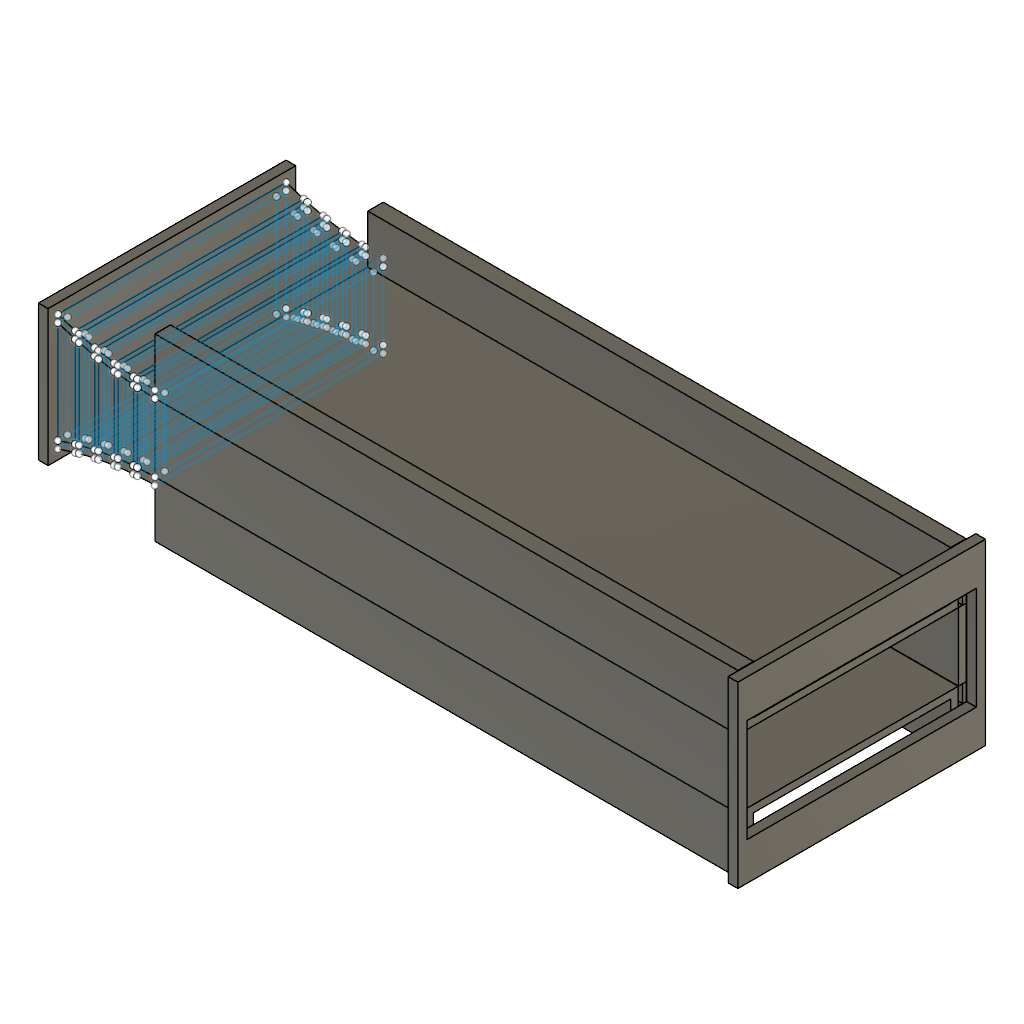
Magnetide-A-printable (Autodesk Fusion 360 design; units mm, degrees)
part number: 2026-10-21-00-04-49-115
Autodesk Fusion 360 part; units mm, degrees
ref_plane "WorkPlane1" through (60, 0, 0) normal (1, 0, 0) x (0, 1, 0)
sketch "plate_a" plane through (60, 0, 0) normal (1, 0, 0) x (0, 0, -1)
  line L0 (-7, -21.85) -> (-7, 21.85)
  line L1 (-7, 21.85) -> (-10.5, 21.85)
  line L2 (-10.5, 21.85) -> (-10.5, 22.75)
  line L3 (-10.5, 22.75) -> (-7, 22.75)
  line L4 (-7, 22.75) -> (-7, 23.5)
  line L5 (-7, 23.5) -> (-18.5, 23.5)
  line L6 (-18.5, 23.5) -> (-18.5, 20.3)
  line L7 (-18.5, 20.3) -> (-8.5, 20.3)
  line L8 (-8.5, 20.3) -> (-8.5, -20.3)
  line L9 (-8.5, -20.3) -> (-18.5, -20.3)
  line L10 (-18.5, -20.3) -> (-18.5, -23.5)
  line L11 (-18.5, -23.5) -> (-7, -23.5)
  line L12 (-7, -23.5) -> (-7, -22.75)
  line L13 (-7, -22.75) -> (-10.5, -22.75)
  line L14 (-10.5, -22.75) -> (-10.5, -21.85)
  line L15 (-10.5, -21.85) -> (-7, -21.85)
extrude "Extrude1" add sketch "plate_a" along normal mid plane 120 makes body 1
ref_plane "WorkPlane2" through (60, 0, 0) normal (1, 0, 0) x (0, 1, 0)
sketch "plate_b" plane through (60, 0, 0) normal (1, 0, 0) x (0, 0, -1)
  line L0 (7, -21.85) -> (7, 21.85)
  line L1 (7, 21.85) -> (10.5, 21.85)
  line L2 (10.5, 21.85) -> (10.5, 22.75)
  line L3 (10.5, 22.75) -> (7, 22.75)
  line L4 (7, 22.75) -> (7, 23.5)
  line L5 (7, 23.5) -> (18.5, 23.5)
  line L6 (18.5, 23.5) -> (18.5, 20.3)
  line L7 (18.5, 20.3) -> (8.5, 20.3)
  line L8 (8.5, 20.3) -> (8.5, -20.3)
  line L9 (8.5, -20.3) -> (18.5, -20.3)
  line L10 (18.5, -20.3) -> (18.5, -23.5)
  line L11 (18.5, -23.5) -> (7, -23.5)
  line L12 (7, -23.5) -> (7, -22.75)
  line L13 (7, -22.75) -> (10.5, -22.75)
  line L14 (10.5, -22.75) -> (10.5, -21.85)
  line L15 (10.5, -21.85) -> (7, -21.85)
extrude "Extrude2" add sketch "plate_b" along normal mid plane 120 separate body makes body 2
ref_plane "WorkPlane3" through (0, -22.7, 0) normal (0, 1, 0) x (0, 0, 1)
sketch "rail_left" plane through (0, -22.7, 0) normal (0, 1, 0) x (1, 0, 0)
  line L0 (0, 7) -> (120, 7)
  line L1 (120, 7) -> (120, -7)
  line L2 (120, -7) -> (0, -7)
  line L3 (0, -7) -> (0, 7)
extrude "Extrude3" add sketch "rail_left" along normal mid plane 1.6 separate body makes body 3
ref_plane "WorkPlane4" through (0, 22.7, 0) normal (0, 1, 0) x (0, 0, 1)
sketch "rail_right" plane through (0, 22.7, 0) normal (0, 1, 0) x (1, 0, 0)
  line L0 (0, 7) -> (120, 7)
  line L1 (120, 7) -> (120, -7)
  line L2 (120, -7) -> (0, -7)
  line L3 (0, -7) -> (0, 7)
extrude "Extrude4" add sketch "rail_right" along normal mid plane 1.6 separate body makes body 4
ref_plane "WorkPlane5" through (-20, 0, 0) normal (1, 0, 0) x (0, 1, 0)
sketch "Sketch5" plane through (-20, 0, 0) normal (1, 0, 0) x (0, 0, -1)
  line L0 (-12, -23.5) -> (-10.5, -23.5)
  line L1 (-10.5, -23.5) -> (-10.5, 23.5)
  line L2 (-10.5, 23.5) -> (-12, 23.5)
  line L3 (-12, 23.5) -> (-12, -23.5)
ref_plane "WorkPlane6" through (-15.6, 0, 0) normal (1, 0, 0) x (0, 1, 0)
sketch "Sketch6" plane through (-15.6, 0, 0) normal (1, 0, 0) x (0, 0, -1)
  line L0 (-10.6294, -23.5) -> (-9.1294, -23.5)
  line L1 (-9.1294, -23.5) -> (-9.1294, 23.5)
  line L2 (-9.1294, 23.5) -> (-10.6294, 23.5)
  line L3 (-10.6294, 23.5) -> (-10.6294, -23.5)
loft "Loft1" add profiles "Sketch5", "Sketch6" section 1 section 2 separate body makes body 5
ref_plane "WorkPlane7" through (-16.4, 0, 0) normal (1, 0, 0) x (0, 1, 0)
sketch "Sketch7" plane through (-16.4, 0, 0) normal (1, 0, 0) x (0, 0, -1)
  line L0 (-10.8534, -23.5) -> (-9.3534, -23.5)
  line L1 (-9.3534, -23.5) -> (-9.3534, 23.5)
  line L2 (-9.3534, 23.5) -> (-10.8534, 23.5)
  line L3 (-10.8534, 23.5) -> (-10.8534, -23.5)
ref_plane "WorkPlane8" through (-11.6, 0, 0) normal (1, 0, 0) x (0, 1, 0)
sketch "Sketch8" plane through (-11.6, 0, 0) normal (1, 0, 0) x (0, 0, -1)
  line L0 (-9.6774, -23.5) -> (-8.1774, -23.5)
  line L1 (-8.1774, -23.5) -> (-8.1774, 23.5)
  line L2 (-8.1774, 23.5) -> (-9.6774, 23.5)
  line L3 (-9.6774, 23.5) -> (-9.6774, -23.5)
loft "Loft2" add profiles "Sketch7", "Sketch8" section 1 section 2 separate body makes body 6
ref_plane "WorkPlane9" through (-12.4, 0, 0) normal (1, 0, 0) x (0, 1, 0)
sketch "Sketch9" plane through (-12.4, 0, 0) normal (1, 0, 0) x (0, 0, -1)
  line L0 (-9.8454, -23.5) -> (-8.3454, -23.5)
  line L1 (-8.3454, -23.5) -> (-8.3454, 23.5)
  line L2 (-8.3454, 23.5) -> (-9.8454, 23.5)
  line L3 (-9.8454, 23.5) -> (-9.8454, -23.5)
ref_plane "WorkPlane10" through (-7.6, 0, 0) normal (1, 0, 0) x (0, 1, 0)
sketch "Sketch10" plane through (-7.6, 0, 0) normal (1, 0, 0) x (0, 0, -1)
  line L0 (-9.0054, -23.5) -> (-7.5054, -23.5)
  line L1 (-7.5054, -23.5) -> (-7.5054, 23.5)
  line L2 (-7.5054, 23.5) -> (-9.0054, 23.5)
  line L3 (-9.0054, 23.5) -> (-9.0054, -23.5)
loft "Loft3" add profiles "Sketch9", "Sketch10" section 1 section 2 separate body makes body 7
ref_plane "WorkPlane11" through (-8.4, 0, 0) normal (1, 0, 0) x (0, 1, 0)
sketch "Sketch11" plane through (-8.4, 0, 0) normal (1, 0, 0) x (0, 0, -1)
  line L0 (-9.1174, -23.5) -> (-7.6174, -23.5)
  line L1 (-7.6174, -23.5) -> (-7.6174, 23.5)
  line L2 (-7.6174, 23.5) -> (-9.1174, 23.5)
  line L3 (-9.1174, 23.5) -> (-9.1174, -23.5)
ref_plane "WorkPlane12" through (-3.6, 0, 0) normal (1, 0, 0) x (0, 1, 0)
sketch "Sketch12" plane through (-3.6, 0, 0) normal (1, 0, 0) x (0, 0, -1)
  line L0 (-8.6134, -23.5) -> (-7.1134, -23.5)
  line L1 (-7.1134, -23.5) -> (-7.1134, 23.5)
  line L2 (-7.1134, 23.5) -> (-8.6134, 23.5)
  line L3 (-8.6134, 23.5) -> (-8.6134, -23.5)
loft "Loft4" add profiles "Sketch11", "Sketch12" section 1 section 2 separate body makes body 8
ref_plane "WorkPlane13" through (-4.4, 0, 0) normal (1, 0, 0) x (0, 1, 0)
sketch "Sketch13" plane through (-4.4, 0, 0) normal (1, 0, 0) x (0, 0, -1)
  line L0 (-8.6694, -23.5) -> (-7.1694, -23.5)
  line L1 (-7.1694, -23.5) -> (-7.1694, 23.5)
  line L2 (-7.1694, 23.5) -> (-8.6694, 23.5)
  line L3 (-8.6694, 23.5) -> (-8.6694, -23.5)
ref_plane "WorkPlane14" through (0, 0, 0) normal (1, 0, 0) x (0, 1, 0)
sketch "Sketch14" plane through (0, 0, 0) normal (1, 0, 0) x (0, 0, -1)
  line L0 (-8.5, -23.5) -> (-7, -23.5)
  line L1 (-7, -23.5) -> (-7, 23.5)
  line L2 (-7, 23.5) -> (-8.5, 23.5)
  line L3 (-8.5, 23.5) -> (-8.5, -23.5)
loft "Loft5" add profiles "Sketch13", "Sketch14" section 1 section 2 separate body makes body 9
ref_plane "WorkPlane15" through (-20, 0, 0) normal (1, 0, 0) x (0, 1, 0)
sketch "Sketch15" plane through (-20, 0, 0) normal (1, 0, 0) x (0, 0, -1)
  line L0 (10.5, -23.5) -> (12, -23.5)
  line L1 (12, -23.5) -> (12, 23.5)
  line L2 (12, 23.5) -> (10.5, 23.5)
  line L3 (10.5, 23.5) -> (10.5, -23.5)
ref_plane "WorkPlane16" through (-15.6, 0, 0) normal (1, 0, 0) x (0, 1, 0)
sketch "Sketch16" plane through (-15.6, 0, 0) normal (1, 0, 0) x (0, 0, -1)
  line L0 (9.1294, -23.5) -> (10.6294, -23.5)
  line L1 (10.6294, -23.5) -> (10.6294, 23.5)
  line L2 (10.6294, 23.5) -> (9.1294, 23.5)
  line L3 (9.1294, 23.5) -> (9.1294, -23.5)
loft "Loft6" add profiles "Sketch15", "Sketch16" section 1 section 2 separate body makes body 10
ref_plane "WorkPlane17" through (-16.4, 0, 0) normal (1, 0, 0) x (0, 1, 0)
sketch "Sketch17" plane through (-16.4, 0, 0) normal (1, 0, 0) x (0, 0, -1)
  line L0 (9.3534, -23.5) -> (10.8534, -23.5)
  line L1 (10.8534, -23.5) -> (10.8534, 23.5)
  line L2 (10.8534, 23.5) -> (9.3534, 23.5)
  line L3 (9.3534, 23.5) -> (9.3534, -23.5)
ref_plane "WorkPlane18" through (-11.6, 0, 0) normal (1, 0, 0) x (0, 1, 0)
sketch "Sketch18" plane through (-11.6, 0, 0) normal (1, 0, 0) x (0, 0, -1)
  line L0 (8.1774, -23.5) -> (9.6774, -23.5)
  line L1 (9.6774, -23.5) -> (9.6774, 23.5)
  line L2 (9.6774, 23.5) -> (8.1774, 23.5)
  line L3 (8.1774, 23.5) -> (8.1774, -23.5)
loft "Loft7" add profiles "Sketch17", "Sketch18" section 1 section 2 separate body makes body 11
ref_plane "WorkPlane19" through (-12.4, 0, 0) normal (1, 0, 0) x (0, 1, 0)
sketch "Sketch19" plane through (-12.4, 0, 0) normal (1, 0, 0) x (0, 0, -1)
  line L0 (8.3454, -23.5) -> (9.8454, -23.5)
  line L1 (9.8454, -23.5) -> (9.8454, 23.5)
  line L2 (9.8454, 23.5) -> (8.3454, 23.5)
  line L3 (8.3454, 23.5) -> (8.3454, -23.5)
ref_plane "WorkPlane20" through (-7.6, 0, 0) normal (1, 0, 0) x (0, 1, 0)
sketch "Sketch20" plane through (-7.6, 0, 0) normal (1, 0, 0) x (0, 0, -1)
  line L0 (7.5054, -23.5) -> (9.0054, -23.5)
  line L1 (9.0054, -23.5) -> (9.0054, 23.5)
  line L2 (9.0054, 23.5) -> (7.5054, 23.5)
  line L3 (7.5054, 23.5) -> (7.5054, -23.5)
loft "Loft8" add profiles "Sketch19", "Sketch20" section 1 section 2 separate body makes body 12
ref_plane "WorkPlane21" through (-8.4, 0, 0) normal (1, 0, 0) x (0, 1, 0)
sketch "Sketch21" plane through (-8.4, 0, 0) normal (1, 0, 0) x (0, 0, -1)
  line L0 (7.6174, -23.5) -> (9.1174, -23.5)
  line L1 (9.1174, -23.5) -> (9.1174, 23.5)
  line L2 (9.1174, 23.5) -> (7.6174, 23.5)
  line L3 (7.6174, 23.5) -> (7.6174, -23.5)
ref_plane "WorkPlane22" through (-3.6, 0, 0) normal (1, 0, 0) x (0, 1, 0)
sketch "Sketch22" plane through (-3.6, 0, 0) normal (1, 0, 0) x (0, 0, -1)
  line L0 (7.1134, -23.5) -> (8.6134, -23.5)
  line L1 (8.6134, -23.5) -> (8.6134, 23.5)
  line L2 (8.6134, 23.5) -> (7.1134, 23.5)
  line L3 (7.1134, 23.5) -> (7.1134, -23.5)
loft "Loft9" add profiles "Sketch21", "Sketch22" section 1 section 2 separate body makes body 13
ref_plane "WorkPlane23" through (-4.4, 0, 0) normal (1, 0, 0) x (0, 1, 0)
sketch "Sketch23" plane through (-4.4, 0, 0) normal (1, 0, 0) x (0, 0, -1)
  line L0 (7.1694, -23.5) -> (8.6694, -23.5)
  line L1 (8.6694, -23.5) -> (8.6694, 23.5)
  line L2 (8.6694, 23.5) -> (7.1694, 23.5)
  line L3 (7.1694, 23.5) -> (7.1694, -23.5)
ref_plane "WorkPlane24" through (0, 0, 0) normal (1, 0, 0) x (0, 1, 0)
sketch "Sketch24" plane through (0, 0, 0) normal (1, 0, 0) x (0, 0, -1)
  line L0 (7, -23.5) -> (8.5, -23.5)
  line L1 (8.5, -23.5) -> (8.5, 23.5)
  line L2 (8.5, 23.5) -> (7, 23.5)
  line L3 (7, 23.5) -> (7, -23.5)
loft "Loft10" add profiles "Sketch23", "Sketch24" section 1 section 2 separate body makes body 14
ref_plane "WorkPlane25" through (-20, 0, 0) normal (1, 0, 0) x (0, 1, 0)
sketch "Sketch25" plane through (-20, 0, 0) normal (1, 0, 0) x (0, 0, -1)
  line L0 (-10.5, -23.5) -> (10.5, -23.5)
  line L1 (10.5, -23.5) -> (10.5, -21.5)
  line L2 (10.5, -21.5) -> (-10.5, -21.5)
  line L3 (-10.5, -21.5) -> (-10.5, -23.5)
ref_plane "WorkPlane26" through (-15.6, 0, 0) normal (1, 0, 0) x (0, 1, 0)
sketch "Sketch26" plane through (-15.6, 0, 0) normal (1, 0, 0) x (0, 0, -1)
  line L0 (-9.1294, -23.5) -> (9.1294, -23.5)
  line L1 (9.1294, -23.5) -> (9.1294, -21.5)
  line L2 (9.1294, -21.5) -> (-9.1294, -21.5)
  line L3 (-9.1294, -21.5) -> (-9.1294, -23.5)
loft "Loft11" add profiles "Sketch25", "Sketch26" section 1 section 2 separate body makes body 15
ref_plane "WorkPlane27" through (-16.4, 0, 0) normal (1, 0, 0) x (0, 1, 0)
sketch "Sketch27" plane through (-16.4, 0, 0) normal (1, 0, 0) x (0, 0, -1)
  line L0 (-9.3534, -23.5) -> (9.3534, -23.5)
  line L1 (9.3534, -23.5) -> (9.3534, -21.5)
  line L2 (9.3534, -21.5) -> (-9.3534, -21.5)
  line L3 (-9.3534, -21.5) -> (-9.3534, -23.5)
ref_plane "WorkPlane28" through (-11.6, 0, 0) normal (1, 0, 0) x (0, 1, 0)
sketch "Sketch28" plane through (-11.6, 0, 0) normal (1, 0, 0) x (0, 0, -1)
  line L0 (-8.1774, -23.5) -> (8.1774, -23.5)
  line L1 (8.1774, -23.5) -> (8.1774, -21.5)
  line L2 (8.1774, -21.5) -> (-8.1774, -21.5)
  line L3 (-8.1774, -21.5) -> (-8.1774, -23.5)
loft "Loft12" add profiles "Sketch27", "Sketch28" section 1 section 2 separate body makes body 16
ref_plane "WorkPlane29" through (-12.4, 0, 0) normal (1, 0, 0) x (0, 1, 0)
sketch "Sketch29" plane through (-12.4, 0, 0) normal (1, 0, 0) x (0, 0, -1)
  line L0 (-8.3454, -23.5) -> (8.3454, -23.5)
  line L1 (8.3454, -23.5) -> (8.3454, -21.5)
  line L2 (8.3454, -21.5) -> (-8.3454, -21.5)
  line L3 (-8.3454, -21.5) -> (-8.3454, -23.5)
ref_plane "WorkPlane30" through (-7.6, 0, 0) normal (1, 0, 0) x (0, 1, 0)
sketch "Sketch30" plane through (-7.6, 0, 0) normal (1, 0, 0) x (0, 0, -1)
  line L0 (-7.5054, -23.5) -> (7.5054, -23.5)
  line L1 (7.5054, -23.5) -> (7.5054, -21.5)
  line L2 (7.5054, -21.5) -> (-7.5054, -21.5)
  line L3 (-7.5054, -21.5) -> (-7.5054, -23.5)
loft "Loft13" add profiles "Sketch29", "Sketch30" section 1 section 2 separate body makes body 17
ref_plane "WorkPlane31" through (-8.4, 0, 0) normal (1, 0, 0) x (0, 1, 0)
sketch "Sketch31" plane through (-8.4, 0, 0) normal (1, 0, 0) x (0, 0, -1)
  line L0 (-7.6174, -23.5) -> (7.6174, -23.5)
  line L1 (7.6174, -23.5) -> (7.6174, -21.5)
  line L2 (7.6174, -21.5) -> (-7.6174, -21.5)
  line L3 (-7.6174, -21.5) -> (-7.6174, -23.5)
ref_plane "WorkPlane32" through (-3.6, 0, 0) normal (1, 0, 0) x (0, 1, 0)
sketch "Sketch32" plane through (-3.6, 0, 0) normal (1, 0, 0) x (0, 0, -1)
  line L0 (-7.1134, -23.5) -> (7.1134, -23.5)
  line L1 (7.1134, -23.5) -> (7.1134, -21.5)
  line L2 (7.1134, -21.5) -> (-7.1134, -21.5)
  line L3 (-7.1134, -21.5) -> (-7.1134, -23.5)
loft "Loft14" add profiles "Sketch31", "Sketch32" section 1 section 2 separate body makes body 18
ref_plane "WorkPlane33" through (-4.4, 0, 0) normal (1, 0, 0) x (0, 1, 0)
sketch "Sketch33" plane through (-4.4, 0, 0) normal (1, 0, 0) x (0, 0, -1)
  line L0 (-7.1694, -23.5) -> (7.1694, -23.5)
  line L1 (7.1694, -23.5) -> (7.1694, -21.5)
  line L2 (7.1694, -21.5) -> (-7.1694, -21.5)
  line L3 (-7.1694, -21.5) -> (-7.1694, -23.5)
ref_plane "WorkPlane34" through (0, 0, 0) normal (1, 0, 0) x (0, 1, 0)
sketch "Sketch34" plane through (0, 0, 0) normal (1, 0, 0) x (0, 0, -1)
  line L0 (-7, -23.5) -> (7, -23.5)
  line L1 (7, -23.5) -> (7, -21.5)
  line L2 (7, -21.5) -> (-7, -21.5)
  line L3 (-7, -21.5) -> (-7, -23.5)
loft "Loft15" add profiles "Sketch33", "Sketch34" section 1 section 2 separate body makes body 19
ref_plane "WorkPlane35" through (-20, 0, 0) normal (1, 0, 0) x (0, 1, 0)
sketch "Sketch35" plane through (-20, 0, 0) normal (1, 0, 0) x (0, 0, -1)
  line L0 (-10.5, 21.5) -> (10.5, 21.5)
  line L1 (10.5, 21.5) -> (10.5, 23.5)
  line L2 (10.5, 23.5) -> (-10.5, 23.5)
  line L3 (-10.5, 23.5) -> (-10.5, 21.5)
ref_plane "WorkPlane36" through (-15.6, 0, 0) normal (1, 0, 0) x (0, 1, 0)
sketch "Sketch36" plane through (-15.6, 0, 0) normal (1, 0, 0) x (0, 0, -1)
  line L0 (-9.1294, 21.5) -> (9.1294, 21.5)
  line L1 (9.1294, 21.5) -> (9.1294, 23.5)
  line L2 (9.1294, 23.5) -> (-9.1294, 23.5)
  line L3 (-9.1294, 23.5) -> (-9.1294, 21.5)
loft "Loft16" add profiles "Sketch35", "Sketch36" section 1 section 2 separate body makes body 20
ref_plane "WorkPlane37" through (-16.4, 0, 0) normal (1, 0, 0) x (0, 1, 0)
sketch "Sketch37" plane through (-16.4, 0, 0) normal (1, 0, 0) x (0, 0, -1)
  line L0 (-9.3534, 21.5) -> (9.3534, 21.5)
  line L1 (9.3534, 21.5) -> (9.3534, 23.5)
  line L2 (9.3534, 23.5) -> (-9.3534, 23.5)
  line L3 (-9.3534, 23.5) -> (-9.3534, 21.5)
ref_plane "WorkPlane38" through (-11.6, 0, 0) normal (1, 0, 0) x (0, 1, 0)
sketch "Sketch38" plane through (-11.6, 0, 0) normal (1, 0, 0) x (0, 0, -1)
  line L0 (-8.1774, 21.5) -> (8.1774, 21.5)
  line L1 (8.1774, 21.5) -> (8.1774, 23.5)
  line L2 (8.1774, 23.5) -> (-8.1774, 23.5)
  line L3 (-8.1774, 23.5) -> (-8.1774, 21.5)
loft "Loft17" add profiles "Sketch37", "Sketch38" section 1 section 2 separate body makes body 21
ref_plane "WorkPlane39" through (-12.4, 0, 0) normal (1, 0, 0) x (0, 1, 0)
sketch "Sketch39" plane through (-12.4, 0, 0) normal (1, 0, 0) x (0, 0, -1)
  line L0 (-8.3454, 21.5) -> (8.3454, 21.5)
  line L1 (8.3454, 21.5) -> (8.3454, 23.5)
  line L2 (8.3454, 23.5) -> (-8.3454, 23.5)
  line L3 (-8.3454, 23.5) -> (-8.3454, 21.5)
ref_plane "WorkPlane40" through (-7.6, 0, 0) normal (1, 0, 0) x (0, 1, 0)
sketch "Sketch40" plane through (-7.6, 0, 0) normal (1, 0, 0) x (0, 0, -1)
  line L0 (-7.5054, 21.5) -> (7.5054, 21.5)
  line L1 (7.5054, 21.5) -> (7.5054, 23.5)
  line L2 (7.5054, 23.5) -> (-7.5054, 23.5)
  line L3 (-7.5054, 23.5) -> (-7.5054, 21.5)
loft "Loft18" add profiles "Sketch39", "Sketch40" section 1 section 2 separate body makes body 22
ref_plane "WorkPlane41" through (-8.4, 0, 0) normal (1, 0, 0) x (0, 1, 0)
sketch "Sketch41" plane through (-8.4, 0, 0) normal (1, 0, 0) x (0, 0, -1)
  line L0 (-7.6174, 21.5) -> (7.6174, 21.5)
  line L1 (7.6174, 21.5) -> (7.6174, 23.5)
  line L2 (7.6174, 23.5) -> (-7.6174, 23.5)
  line L3 (-7.6174, 23.5) -> (-7.6174, 21.5)
ref_plane "WorkPlane42" through (-3.6, 0, 0) normal (1, 0, 0) x (0, 1, 0)
sketch "Sketch42" plane through (-3.6, 0, 0) normal (1, 0, 0) x (0, 0, -1)
  line L0 (-7.1134, 21.5) -> (7.1134, 21.5)
  line L1 (7.1134, 21.5) -> (7.1134, 23.5)
  line L2 (7.1134, 23.5) -> (-7.1134, 23.5)
  line L3 (-7.1134, 23.5) -> (-7.1134, 21.5)
loft "Loft19" add profiles "Sketch41", "Sketch42" section 1 section 2 separate body makes body 23
ref_plane "WorkPlane43" through (-4.4, 0, 0) normal (1, 0, 0) x (0, 1, 0)
sketch "Sketch43" plane through (-4.4, 0, 0) normal (1, 0, 0) x (0, 0, -1)
  line L0 (-7.1694, 21.5) -> (7.1694, 21.5)
  line L1 (7.1694, 21.5) -> (7.1694, 23.5)
  line L2 (7.1694, 23.5) -> (-7.1694, 23.5)
  line L3 (-7.1694, 23.5) -> (-7.1694, 21.5)
ref_plane "WorkPlane44" through (0, 0, 0) normal (1, 0, 0) x (0, 1, 0)
sketch "Sketch44" plane through (0, 0, 0) normal (1, 0, 0) x (0, 0, -1)
  line L0 (-7, 21.5) -> (7, 21.5)
  line L1 (7, 21.5) -> (7, 23.5)
  line L2 (7, 23.5) -> (-7, 23.5)
  line L3 (-7, 23.5) -> (-7, 21.5)
loft "Loft20" add profiles "Sketch43", "Sketch44" section 1 section 2 separate body makes body 24
ref_plane "WorkPlane45" through (-21, 0, 0) normal (1, 0, 0) x (0, 1, 0)
sketch "front_flange" plane through (-21, 0, 0) normal (1, 0, 0) x (0, 0, -1)
  line L0 (-14, -25.5) -> (14, -25.5)
  line L1 (14, -25.5) -> (14, 25.5)
  line L2 (14, 25.5) -> (-14, 25.5)
  line L3 (-14, 25.5) -> (-14, -25.5)
  line L4 (-10.5, -23.5) -> (-10.5, 23.5)
  line L5 (-10.5, 23.5) -> (10.5, 23.5)
  line L6 (10.5, 23.5) -> (10.5, -23.5)
  line L7 (10.5, -23.5) -> (-10.5, -23.5)
extrude "Extrude5" add sketch "front_flange" along normal mid plane 2 separate body makes body 25
ref_plane "WorkPlane46" through (121, 0, 0) normal (1, 0, 0) x (0, 1, 0)
sketch "rear_cap" plane through (121, 0, 0) normal (1, 0, 0) x (0, 0, -1)
  line L0 (-18.4, -25.5) -> (18.4, -25.5)
  line L1 (18.4, -25.5) -> (18.4, 25.5)
  line L2 (18.4, 25.5) -> (-18.4, 25.5)
  line L3 (-18.4, 25.5) -> (-18.4, -25.5)
  line L4 (-10.6, -23.6) -> (10.6, -23.6)
  line L5 (10.6, -23.6) -> (10.6, 23.6)
  line L6 (10.6, 23.6) -> (-10.6, 23.6)
  line L7 (-10.6, 23.6) -> (-10.6, -23.6)
extrude "Extrude6" add sketch "rear_cap" along normal mid plane 2 separate body makes body 26
named bodies: "plate_a", "plate_b", "rail_left", "rail_right", "bm_top_s00", "bm_top_s01", "bm_top_s02", "bm_top_s03", "bm_top_s04", "bm_bottom_s00", "bm_bottom_s01", "bm_bottom_s02", "bm_bottom_s03", "bm_bottom_s04", "bm_left_s00", "bm_left_s01", "bm_left_s02", "bm_left_s03", "bm_left_s04", "bm_right_s00", "bm_right_s01", "bm_right_s02", "bm_right_s03", "bm_right_s04", "front_flange", "rear_cap"
